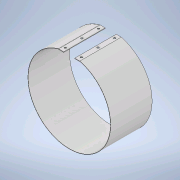
# Autodesk Inventor part: Rotorschutz_BT1
Saved by Autodesk Inventor 2020.1 (Build 241239000, 239)
## iProperties
Created: 2020-08-20
Part Number: Rotorschutz_BT1
Material: Generisch
Document SubType Name: Modeling
Designer: s5chfeis
Density: 1 g/cm^3
Appearance: Vorgabe
Author: s5chfeis
Autodesk Inventor part; units mm, degrees
ref_plane "YZ Plane" through (0, 0, 0) normal (1, 0, 0) x (0, 1, 0)
ref_plane "XZ Plane" through (0, 0, 0) normal (0, 1, 0) x (-1, 0, 0)
ref_plane "XY Plane" through (0, 0, 0) normal (0, 0, 1) x (1, 0, 0)
sketch "Skizze2" plane through (0, 0, 0) normal (0, 0, 1) x (1, 0, 0)
  circle A0 centre (0, 0) radius 150
  circle A1 centre (0, 0) radius 149
  dimension "d0" = 300
  dimension "d1" = 298
  constraints: 2 centre point, 2 coincident
  measures "d0" diameter of A0
  measures "d1" diameter of A1
extrude "Extrusion1" add sketch "Skizze2" along normal blind 150
sketch "Skizze3" plane through (0, 0, 150) normal (0, 0, 1) x (1, 0, 0)
  line L0 (0, 0) -> (0, 145)
  line L1 (0, 145) -> (-50, 145)
  line L2 (-50, 145) -> (-50, 155)
  line L3 (-50, 155) -> (50, 155)
  line L4 (50, 155) -> (50, 145)
  line L5 (50, 145) -> (0, 145)
  dimension "d4" = 145
  dimension "d5" = 50
  dimension "d6" = 10
  dimension "d7" = 90
  dimension "d8" = 100
  dimension "d9" = 90
  dimension "d10" = 10
  dimension "d11" = 270
  constraints: 12 end point, 4 perpendicular, 1 vertical
  measures "d4" distance of L0.start L0.end
  measures "d5" distance of L0.end L1.end
  measures "d6" distance of L1.end L2.end
  measures "d7" angle of L1 L2
  measures "d8" distance of L2.end L3.end
  measures "d9" angle of L2 L3
  measures "d10" distance of L3.end L4.end
extrude "Extrusion2" cut sketch "Skizze3" against normal blind 150
sketch "Skizze4" plane through (-38.4057, 145, 150) normal (0, 1, 0) x (1, 0, 0)
  line L0 (76.8115, 150) -> (76.8115, 0) projected
  line L1 (0, 150) -> (76.8115, 150)
  line L2 (76.8115, 150) -> (76.8115, 0)
  line L3 (76.8115, 0) -> (0, 0)
  line L4 (0, 0) -> (0, 150)
  point P0 (38.4057, 150)
  constraints: 8 end point, 2 parallel, 1 horizontal, 1 perpendicular
extrude "Extrusion3" add sketch "Skizze4" against normal blind 2
sketch "Skizze5" plane through (0, 0, 150) normal (0, 0, 1) x (1, 0, 0)
  line L0 (-38.4057, 143.9653) -> (-38.4057, 143) projected
  line L1 (-38.4057, 143) -> (-41.8569, 143)
  line L2 (38.4057, 143.9653) -> (38.4057, 143) projected
  line L3 (38.4057, 143) -> (41.8235, 143)
  line L4 (38.4057, 143) -> (38.4057, 143.9653)
  arc A0 (-38.4057, 143.9653) -> (38.4057, 143.9653) centre (0, 0) ccw projected
  line L5 (41.8235, 143) -> (38.4057, 143)
  line L6 (38.4057, 143) -> (38.4057, 143.9653)
  line L7 (38.4057, 143.9653) -> (41.8235, 143.9653)
  line L8 (41.8235, 143.9653) -> (41.8235, 143)
  line L9 (-38.4057, 143) -> (38.4057, 143) projected
  line L10 (-38.4057, 143) -> (-41.8569, 143)
  line L11 (-41.8569, 143) -> (-41.8569, 143.9653)
  line L12 (-41.8569, 143.9653) -> (-38.4057, 143.9653)
  line L13 (-38.4057, 143.9653) -> (-38.4057, 143)
  point P0 (41.8235, 143.0098)
  constraints: 22 end point, 4 parallel, 3 horizontal, 2 perpendicular, 2 point on line
extrude "Extrusion4" add sketch "Skizze5" against normal blind 150 contours L0 L1 A0 | L2 A0 L8 L3
sketch "Skizze7" plane through (0, 0, 150) normal (0, 0, 1) x (1, 0, 0)
  line L0 (0, 0) -> (0, 145)
  line L1 (0, 0) -> (145, 0) construction
  line L2 (0, 145) -> (-20, 145)
  line L3 (-20, 145) -> (-20, 140)
  line L4 (-20, 140) -> (0, 140)
  line L5 (0, 140) -> (0, 145)
  line L6 (0, 145) -> (20, 145)
  line L7 (20, 145) -> (20, 140)
  line L8 (20, 140) -> (0, 140)
  line L9 (0, 140) -> (0, 145)
  dimension "d18" = 145
  dimension "d19" = 90
  dimension "d20" = 20
  dimension "d21" = 5
  dimension "d22" = 20
  dimension "d23" = 5
  constraints: 20 end point, 4 parallel, 3 horizontal, 3 perpendicular, 1 vertical
  measures "d18" distance of L0.start L0.end
  measures "d19" angle of L1 L0
  measures "d20" distance of L4.end L3.end
  measures "d21" distance of L3.end L2.end
  measures "d22" distance of L7.end L8.end
  measures "d23" distance of L6.end L7.end
extrude "Extrusion5" cut sketch "Skizze7" against normal blind 150
sketch "Skizze8" plane through (-38.4057, 145, 150) normal (0, 1, 0) x (1, 0, 0)
  line L0 (0, 0) -> (0, 150) construction
  line L1 (18.4057, 0) -> (18.4057, 150) construction
  line L2 (0, 150) -> (18.4057, 0) construction
  line L3 (0, 0) -> (18.4057, 150) construction
  line L4 (9.2029, 75) -> (9.2029, 150) construction
  line L5 (-111.5943, 150) -> (188.4057, 150) construction
  line L6 (9.2029, 75) -> (84.2029, 75) construction
  line L7 (9.2029, 75) -> (9.2029, 0) construction
  line L8 (187.4057, 0) -> (-110.5943, 0) construction
  line L9 (9.2029, 75) -> (84.2029, 75) construction
  line L10 (9.2029, 75) -> (9.2029, 135) construction
  line L11 (9.2029, 75) -> (69.2029, 75) construction
  line L12 (9.2029, 75) -> (9.2029, 15) construction
  line L13 (9.2029, 75) -> (69.2029, 75) construction
  line L14 (38.4057, 150) -> (38.4057, 0) construction
  point P0 (76.8115, 150)
  point P1 (80.2292, 0)
  point P2 (-3.4512, 0)
  point P3 (67.6086, 75)
  point P4 (67.6086, 135)
  point P5 (67.6086, 15)
  dimension "d26" = 75
  dimension "d27" = 90
  dimension "d28" = 75
  dimension "d29" = 90
  dimension "d30" = 60
  dimension "d31" = 90
  dimension "d32" = 60
  dimension "d33" = 90
  constraints: 22 end point, 6 perpendicular, 4 horizontal, 3 coincident, 3 midpoint, 3 symmetric about line, 2 collinear, 1 point on line
  measures "d26" distance of L4.start L4.end
  measures "d27" angle of L6 L4
  measures "d28" distance of L7.start L7.end
  measures "d29" angle of L7 L9
  measures "d30" distance of L10.start L10.end
  measures "d31" angle of L11 L10
  measures "d32" distance of L10.start L12.end
  measures "d33" angle of L12 L13
hole "Bohrung1" at (-29.2029, 145, 75) at (-29.2029, 145, 15) at (-29.2029, 145, 135) at (29.2029, 145, 135) at (29.2029, 145, 75) at (29.2029, 145, 15) direction (0, -1, 0) diameter 7 depth 27.3 tip angle 118
